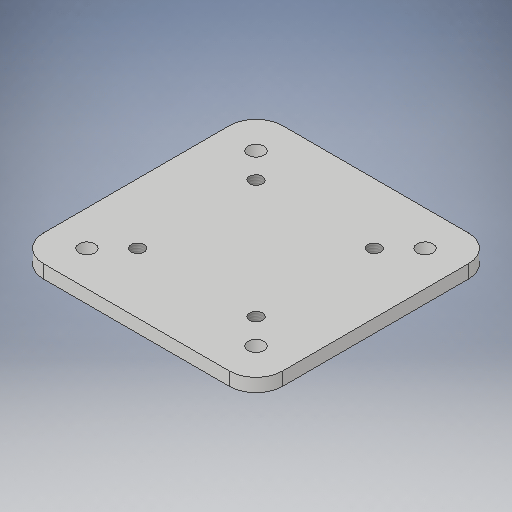
# Autodesk Inventor part: BT018_thutrn22_26
Saved by Autodesk Inventor 2025.3 (Build 293356000, 356)
## iProperties
Company: HTBLA Kaindorf
RuleStatus: InUse
Created: 2026-08-18
Part Number: BT018_thutrn22_26
Project: Biegeroboter
Material: Generisch
Description: gehaeuse_motor_deckel_v2
Document SubType Name: Modeling
Designer: thutrn22
Density: 1 g/cm^3
Appearance: Vorgabe
Mass: 39.1255 g
Surface Area: 180.503 cm^2
Volume: 39.1255 cm^3
AfterDocNew0: iProperties-Editor_aufrufen
Author: trist
Keywords: 2026
Autodesk Inventor part; units mm, degrees
ref_plane "YZ Plane" through (0, 0, 0) normal (1, 0, 0) x (0, 1, 0)
ref_plane "XZ Plane" through (0, 0, 0) normal (0, 1, 0) x (-1, 0, 0)
ref_plane "XY Plane" through (0, 0, 0) normal (0, 0, 1) x (1, 0, 0)
sketch "Skizze3" plane through (0, 0, 0) normal (0, 0, 1) x (1, 0, 0)
  line L0 (-64.8757, 0) -> (64.8757, 0) projected
  line L1 (0, -64.8757) -> (0, 64.8757) projected
  line L2 (-45, 45) -> (45, 45)
  line L3 (45, 45) -> (45, -45)
  line L4 (45, -45) -> (-45, -45)
  line L5 (-45, -45) -> (-45, 45)
  arc A0 (-35, 45) -> (-45, 35) centre (-31.3399, 31.3399) ccw
  arc A1 (45, 35) -> (35, 45) centre (31.3399, 31.3399) ccw
  arc A2 (-45, -35) -> (-35, -45) centre (-31.3399, -31.3399) ccw
  arc A3 (35, -45) -> (45, -35) centre (31.3399, -31.3399) ccw
  point P0 (0, 0)
  dimension "d8" = 90
  dimension "d9" = 90
  dimension "d13" = 70
  dimension "d14" = 35
  dimension "d15" = 35
  dimension "d16" = 70
  dimension "d17" = 70
  dimension "d18" = 35
  dimension "d19" = 70
  dimension "d20" = 35
  dimension "d22" = 14.142
  dimension "d23" = 14.142
  dimension "d24" = 14.142
  dimension "d25" = 14.142
  constraints: 8 end point, 8 point on circle, 8 point on line, 4 centre point, 2 parallel, 1 horizontal, 1 perpendicular, 2 other
  measures "d8" distance of L3.end L4.end
  measures "d9" distance of L2.end L3.end
  measures "d13" distance of A3.start A2.end
  measures "d14" distance from line of L1 A2.end
  measures "d15" distance from line of L0 A3.end
  measures "d16" distance of A3.end A1.start
  measures "d17" distance of A0.start A1.end
  measures "d18" distance from line of L1 A0.start
  measures "d19" distance of A2.start A0.end
  measures "d20" distance from line of L0 A0.end
  measures "d22" radius of A0
  measures "d23" radius of A1
  measures "d24" radius of A2
  measures "d25" radius of A3
extrude "Extrusion3" add sketch "Skizze3" along normal blind 5
sketch "Skizze4" plane through (0, 0, 5) normal (0, 0, 1) x (1, 0, 0)
  line L0 (-63, 0) -> (63, 0) projected
  line L1 (0, -63) -> (0, 63) projected
  line L2 (-31.82, -31.82) -> (31.82, -31.82)
  line L3 (31.82, -31.82) -> (31.82, 31.82)
  line L4 (31.82, 31.82) -> (-31.82, 31.82)
  line L5 (-31.82, 31.82) -> (-31.82, -31.82)
  circle A0 centre (-31.82, -31.82) radius 3
  circle A1 centre (-31.82, 31.82) radius 3
  circle A2 centre (31.82, 31.82) radius 3
  circle A3 centre (31.82, -31.82) radius 3
  dimension "d39" = 63.64
  dimension "d40" = 63.64
  dimension "d41" = 6
  dimension "d42" = 6
  dimension "d43" = 6
  dimension "d44" = 6
  constraints: 8 end point, 4 centre point, 4 coincident, 2 parallel, 1 horizontal, 1 perpendicular, 2 other
  measures "d39" distance of L4.end L3.end
  measures "d40" distance of L3.end L2.end
  measures "d41" diameter of A0
  measures "d42" diameter of A1
  measures "d43" diameter of A2
  measures "d44" diameter of A3
extrude "Extrusion4" cut sketch "Skizze4" against normal blind 10 contours A1 L4 L5 | L5 L4 A1 | A0 L2 L5 | L5 L2 A0 | A3 L2 L3 | L3 L2 A3 | A2 L4 L3 | L3 L4 A2
sketch "Skizze5" plane through (0, 0, 5) normal (0, 0, 1) x (1, 0, 0)
  line L0 (-63, 0) -> (63, 0) projected
  line L1 (0, -63) -> (0, 63) projected
  line L2 (-22.274, -22.274) -> (22.274, -22.274)
  line L3 (22.274, -22.274) -> (22.274, 22.274)
  line L4 (22.274, 22.274) -> (-22.274, 22.274)
  line L5 (-22.274, 22.274) -> (-22.274, -22.274)
  point P0 (0, 0)
  dimension "d47" = 44.548
  dimension "d48" = 44.548
  constraints: 8 end point, 4 coincident, 2 parallel, 1 horizontal, 1 perpendicular, 2 other
  measures "d47" distance of L4.end L3.end
  measures "d48" distance of L3.end L2.end
hole "Bohrung1" at (-22.274, -22.274, 5) at (-22.274, 22.274, 5) at (22.274, 22.274, 5) at (22.274, -22.274, 5) direction (0, 0, -1) diameter 4.917 end through all thread size "M6x1" class "6H" standard "ISO Metric profile"
fillet "Rundung1" radius 10 4 edges at (45, 45, 2.5) (45, -45, 2.5) (-45, 45, 2.5) (-45, -45, 2.5)
